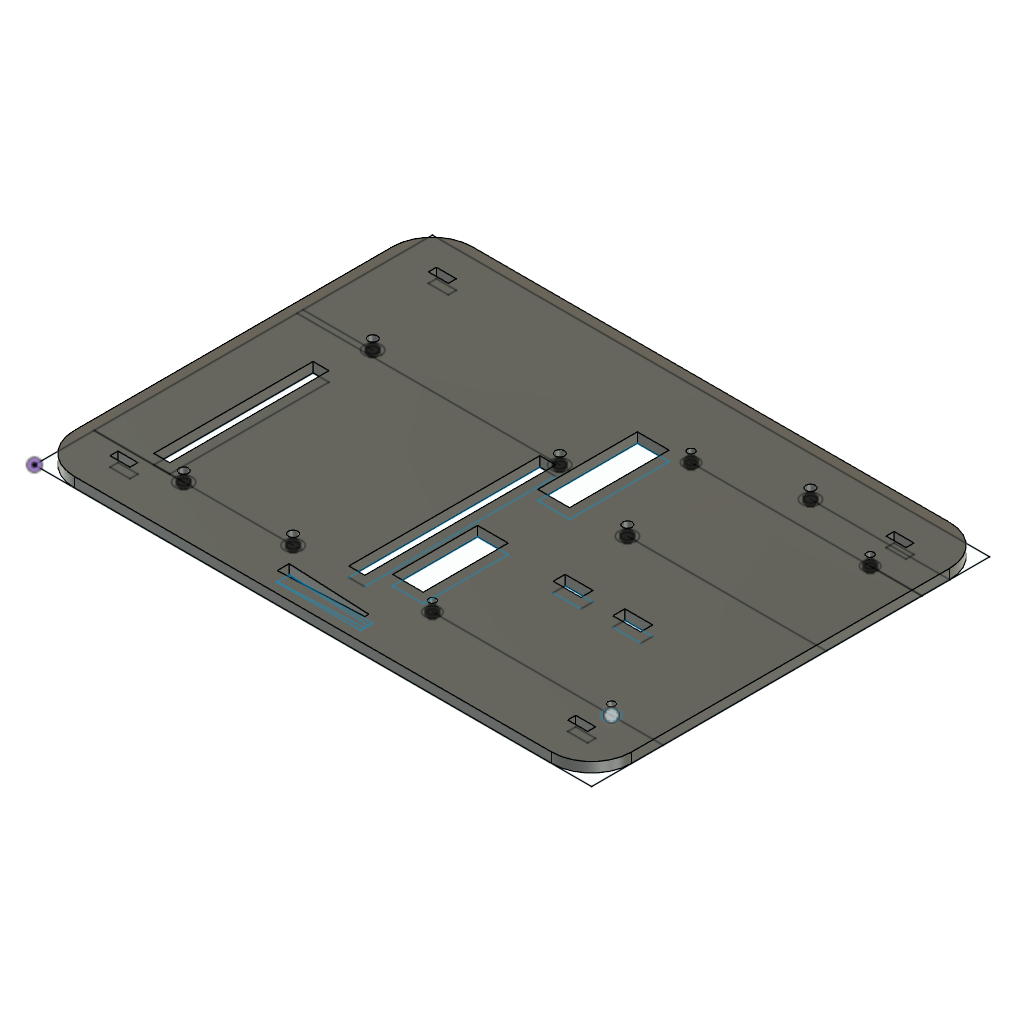
Soporte_electronica (Autodesk Fusion 360 design; units mm, degrees)
part number: 2026-10-02-12-16-42-658
Autodesk Fusion 360 part; units mm, degrees
sketch "Boceto1" plane through (0, 0, 0) normal (0, 0, 1) x (1, 0, 0)
  line L0 (0, 0) -> (140, 0)
  line L1 (140, 0) -> (140, 100)
  line L2 (140, 100) -> (0, 100)
  line L3 (0, 100) -> (0, 0)
  line L4 (10, 11) -> (15, 11)
  line L5 (15, 11) -> (15, 9)
  line L6 (15, 9) -> (10, 9)
  line L7 (10, 9) -> (10, 11)
  line L8 (10, 91) -> (15, 91)
  line L9 (15, 91) -> (15, 89)
  line L10 (15, 89) -> (10, 89)
  line L11 (10, 89) -> (10, 91)
  line L12 (125, 91) -> (130, 91)
  line L13 (130, 91) -> (130, 89)
  line L14 (130, 89) -> (125, 89)
  line L15 (125, 89) -> (125, 91)
  line L16 (125, 11) -> (130, 11)
  line L17 (130, 11) -> (130, 9)
  line L18 (130, 9) -> (125, 9)
  line L19 (125, 9) -> (125, 11)
  line L20 (0, 67.5) -> (17.5, 67.5)
  circle A0 centre (17.5, 67.5) radius 1.15
  line L21 (0, 15) -> (22.5, 15)
  circle A1 centre (22.5, 15) radius 1.15
  line L22 (0, 66) -> (66, 66)
  circle A2 centre (66, 66) radius 1.15
  line L23 (0, 15) -> (50, 15)
  circle A3 centre (50, 15) radius 1.15
  line L24 (19, 15) -> (15, 15)
  line L25 (15, 15) -> (15, 55)
  line L26 (15, 55) -> (19, 55)
  line L27 (19, 55) -> (19, 15)
  line L28 (68, 15) -> (64, 15)
  line L29 (64, 15) -> (64, 63)
  line L30 (64, 63) -> (68, 63)
  line L31 (68, 63) -> (68, 15)
  line L32 (140, 83) -> (127, 83)
  line L33 (140, 83) -> (82, 83)
  circle A4 centre (127, 83) radius 0.9
  circle A5 centre (82, 83) radius 0.9
  line L34 (140, 18) -> (82, 18)
  circle A6 centre (127, 18) radius 0.9
  circle A7 centre (82, 18) radius 0.9
  line L35 (140, 59) -> (90, 59)
  circle A8 centre (90, 59) radius 1.15
  line L36 (140, 90) -> (105, 90)
  circle A9 centre (105, 90) radius 1.15
  line L37 (79.0311, 18.6757) -> (71.3514, 18.6757)
  line L38 (71.3514, 18.6757) -> (71.3514, 40)
  line L39 (71.3514, 40) -> (79.0311, 40)
  line L40 (79.0311, 40) -> (79.0311, 18.6757)
  line L41 (71.0578, 80.4352) -> (79.0311, 80.4352)
  line L42 (79.0311, 80.4352) -> (79.0311, 55.4341)
  line L43 (79.0311, 55.4341) -> (71.0578, 55.4341)
  line L44 (71.0578, 55.4341) -> (71.0578, 80.4352)
  line L45 (56, 8) -> (77, 8)
  line L46 (77, 8) -> (77, 5)
  line L47 (77, 5) -> (56, 5)
  line L48 (56, 5) -> (56, 8)
  line L49 (77, 7) -> (56, 8)
  line L50 (56, 5) -> (77, 6)
  circle A10 centre (22.5, 15) radius 2.15
  circle A11 centre (50, 15) radius 2.15
  circle A12 centre (17.5, 67.5) radius 2.15
  circle A13 centre (66, 66) radius 2.15
  circle A14 centre (105, 90) radius 2.15
  circle A15 centre (90, 59) radius 2.15
  circle A16 centre (82, 83) radius 1.9
  circle A17 centre (127, 83) radius 1.9
  circle A18 centre (82, 18) radius 1.9
  circle A19 centre (127, 18) radius 1.9
  line L51 (93, 40.3522) -> (100, 40.3522)
  line L52 (100, 40.3522) -> (100, 37.3522)
  line L53 (100, 37.3522) -> (93, 37.3522)
  line L54 (93, 37.3522) -> (93, 40.3522)
  line L55 (108, 40.3522) -> (115, 40.3522)
  line L56 (115, 40.3522) -> (115, 37.3522)
  line L57 (115, 37.3522) -> (108, 37.3522)
  line L58 (108, 37.3522) -> (108, 40.3522)
  dimension "d1" = 100
  dimension "d2" = 140
  dimension "d3" = 5
  dimension "d4" = 2
  dimension "d5" = 10
  dimension "d6" = 9
  dimension "d7" = 5
  dimension "d8" = 2
  dimension "d9" = 9
  dimension "d10" = 10
  dimension "d11" = 5
  dimension "d12" = 2
  dimension "d13" = 9
  dimension "d14" = 10
  dimension "d15" = 5
  dimension "d16" = 2
  dimension "d17" = 10
  dimension "d18" = 9
  dimension "d19" = 17.5
  dimension "d20" = 67.5
  dimension "d21" = 2.3
  dimension "d22" = 22.5
  dimension "d23" = 15
  dimension "d24" = 2.3
  dimension "d25" = 66
  dimension "d26" = 66
  dimension "d27" = 2.3
  dimension "d28" = 50
  dimension "d29" = 2.3
  dimension "d30" = 4
  dimension "d31" = 40
  dimension "d32" = 15
  dimension "d33" = 4
  dimension "d34" = 48
  dimension "d35" = 15
  dimension "d36" = 13
  dimension "d37" = 83
  dimension "d38" = 58
  dimension "d39" = 1.8
  dimension "d40" = 1.8
  dimension "d41" = 58
  dimension "d42" = 13
  dimension "d43" = 18
  dimension "d44" = 1.8
  dimension "d45" = 1.8
  dimension "d46" = 45
  dimension "d47" = 65
  dimension "d48" = 50
  dimension "d49" = 59
  dimension "d50" = 2.3
  dimension "d51" = 35
  dimension "d52" = 90
  dimension "d53" = 2.3
  dimension "d54" = 3
  dimension "d55" = 1
  dimension "d56" = 21
  dimension "d57" = 4.3
  dimension "d58" = 4.3
  dimension "d59" = 4.3
  dimension "d60" = 4.3
  dimension "d61" = 4.3
  dimension "d62" = 4.3
  dimension "d63" = 3.8
  dimension "d64" = 3.8
  dimension "d65" = 3.8
  dimension "d66" = 3.8
  dimension "d67" = 7
  dimension "d68" = 7
  dimension "d69" = 3
  dimension "d70" = 3
  dimension "d71" = 25
  dimension "d72" = 40
  constraint horizontal L0
  constraint vertical L1
  constraint horizontal L2
  constraint vertical L3
  constraint coincident L0.start L3.end
  constraint horizontal L4
  constraint vertical L5
  constraint horizontal L6
  constraint vertical L7
  constraint horizontal L8
  constraint vertical L9
  constraint horizontal L10
  constraint vertical L11
  constraint horizontal L12
  constraint vertical L13
  constraint horizontal L14
  constraint vertical L15
  constraint horizontal L16
  constraint vertical L17
  constraint horizontal L18
  constraint vertical L19
  constraint coincident L3 L20.start
  constraint perpendicular L3 L20
  constraint coincident L20.end A0.centre
  constraint coincident L3 L21.start
  constraint perpendicular L5 L21
  constraint coincident L21.end A1.centre
  constraint coincident L3 L22.start
  constraint perpendicular L3 L22
  constraint coincident L22.end A2.centre
  constraint perpendicular L3 L23
  constraint coincident L23.end A3.centre
  constraint horizontal L24
  constraint vertical L25
  constraint horizontal L26
  constraint vertical L27
  constraint coincident L23 L24.start
  constraint horizontal L28
  constraint vertical L29
  constraint horizontal L30
  constraint vertical L31
  constraint coincident L1 L32.start
  constraint perpendicular L1 L32
  constraint perpendicular L1 L33
  constraint coincident L32.end A4.centre
  constraint coincident L33.end A5.centre
  constraint coincident L1 L34.start
  constraint perpendicular L1 L34
  constraint coincident L34.end A7.centre
  constraint coincident L1 L35.start
  constraint perpendicular L1 L35
  constraint coincident L35.end A8.centre
  constraint coincident L1 L36.start
  constraint perpendicular L1 L36
  constraint coincident L36.end A9.centre
  constraint horizontal L37
  constraint vertical L38
  constraint horizontal L39
  constraint vertical L40
  constraint horizontal L41
  constraint vertical L42
  constraint horizontal L43
  constraint vertical L44
  constraint horizontal L45
  constraint vertical L46
  constraint horizontal L47
  constraint vertical L48
  constraint coincident L46 L49.start
  constraint coincident L46 L50.end
  constraint concentric A6 A19
  constraint horizontal L51
  constraint vertical L52
  constraint horizontal L53
  constraint vertical L54
  constraint horizontal L55
  constraint vertical L56
  constraint horizontal L57
  constraint vertical L58
  measures "d1" distance of L0.end L1.end
  measures "d2" distance of L0.start L0.end
  measures "d3" distance of L4.start L4.end
  measures "d4" distance of L4.end L5.end
  measures "d5" distance of L3 L7
  measures "d6" distance of L0 L6
  measures "d7" distance of L9.end L10.end
  measures "d8" distance of L8.end L9.end
  measures "d9" distance of L2 L8
  measures "d10" distance of L3 L11
  measures "d11" distance of L12.start L12.end
  measures "d12" distance of L12.start L14.end
  measures "d13" distance of L2 L12
  measures "d14" distance of L1 L13
  measures "d15" distance of L16.start L16.end
  measures "d16" distance of L16.end L17.end
  measures "d17" distance of L1 L17
  measures "d18" distance of L0 L18
  measures "d19" distance of L20.start L20.end
  measures "d20" distance of L0 L20.end
  measures "d21" diameter of A0
  measures "d22" distance of L21.start L21.end
  measures "d23" distance of L0 L21.end
  measures "d24" diameter of A1
  measures "d25" distance of L22.start L22.end
  measures "d26" distance of L0 L22.end
  measures "d27" diameter of A2
  measures "d28" distance of L21.start L23.end
  measures "d29" diameter of A3
  measures "d30" distance of L25.end L26.end
  measures "d31" distance of L24.start L26.end
  measures "d32" distance of L3 L25
  measures "d33" distance of L28.start L28.end
  measures "d34" distance of L28.start L30.end
  measures "d35" distance of L0 L28
  measures "d36" distance of L32.start L32.end
  measures "d37" distance of L0 L32.end
  measures "d38" distance of L32.start L33.end
  measures "d39" diameter of A4
  measures "d40" diameter of A5
  measures "d41" distance of L34.start L34.end
  measures "d42" distance of L34.start A6.centre
  measures "d43" distance of L0 L34.end
  measures "d44" diameter of A6
  measures "d45" diameter of A7
  measures "d46" distance of L32.end L33.end
  measures "d47" distance of L33.end L34.end
  measures "d48" distance of L35.start L35.end
  measures "d49" distance of L0 L35.end
  measures "d50" diameter of A8
  measures "d51" distance of L36.start L36.end
  measures "d52" distance of L0 L36.end
  measures "d53" diameter of A9
  measures "d54" distance of L45.start L47.end
  measures "d55" distance of L49.start L50.end
  measures "d56" distance of L46.end L47.end
  measures "d57" diameter of A10
  measures "d58" diameter of A11
  measures "d59" diameter of A12
  measures "d60" diameter of A13
  measures "d61" diameter of A14
  measures "d62" diameter of A15
  measures "d63" diameter of A16
  measures "d64" diameter of A17
  measures "d65" diameter of A18
  measures "d66" diameter of A19
  measures "d67" distance of L51.start L51.end
  measures "d68" distance of L55.start L55.end
  measures "d69" distance of L55.end L56.end
  measures "d70" distance of L51.end L52.end
  measures "d71" distance of L1 L56
  measures "d72" distance of L1 L52
extrude "Extruir1" add sketch "Boceto1" along normal blind 2.5 contours L0 L1 L2 L3 L20 L22 A12 | L3 L20 L22 A12 | L45 L46 L49 | L46 L47 L50
fillet "Empalme1" radius 10 3 edges at (0, 0, 1.25) (140, 100, 1.25) (140, 0, 1.25)
extrude "Extruir2" add sketch "Boceto1" along normal blind 2.5 and the other way blind 3 contours L22 A12 | L22 A12 | L21 A1 L23 A10 | L21 A1 L23 A10 | L32 L33 A4 A17 | L32 L33 A4 A17 | L34 A6 A19 | L34 A6 A19 | A11 | A13 | A14 | A15 | A16 | A18
fillet "Empalme2" radius 10 1 edges at (0, 100, 1.25)
